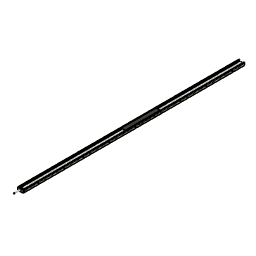
assembly-v21 (Autodesk Fusion 360 archive; units mm, degrees)
design "Linear actuator"
Autodesk Fusion 360 part; units mm, degrees
(part 1 of 2)
sketch "C section" plane through (0, 0, 0) normal (0, 1, 0) x (1, 0, 0)
  line L0 (0, 0) -> (40, 0)
  line L1 (40, 0) -> (40, -20)
  line L2 (0, -20) -> (0, 0)
  line L3 (5, -5) -> (35, -5)
  line L4 (0, -20) -> (5, -20) construction
  line L5 (0, -20) -> (5, -20)
  line L6 (35, -20) -> (40, -20)
  line L7 (34, -20) -> (34, -6.4559) construction
  line L8 (6, -6.4559) -> (6, -20) construction
  line L9 (5, -11) -> (35, -11) construction
  line L10 (5, -15) -> (35, -15) construction
  line L11 (6, -14.25) -> (5, -14.25)
  line L12 (5, -15.75) -> (6, -15.75)
  line L13 (6, -15.75) -> (6, -14.25)
  line L14 (5, -20) -> (5, -15.75)
  line L15 (5, -11.75) -> (6, -11.75)
  line L16 (6, -11.75) -> (6, -10.25)
  line L17 (5, -10.25) -> (6, -10.25)
  line L18 (20, 0) -> (20, -24.6236) construction
  line L19 (34, -14.25) -> (35, -14.25)
  line L20 (35, -15.75) -> (34, -15.75)
  line L21 (34, -15.75) -> (34, -14.25)
  line L22 (35, -11.75) -> (34, -11.75)
  line L23 (35, -10.25) -> (34, -10.25)
  line L24 (34, -11.75) -> (34, -10.25)
  line L25 (35, -15.75) -> (35, -20)
  line L26 (35, -5) -> (35, -10.25)
  line L27 (35, -11.75) -> (35, -14.25)
  line L28 (5, -14.25) -> (5, -11.75)
  line L29 (5, -10.25) -> (5, -5)
  point P0 (5, -15)
  dimension "d1" = 40
  dimension "d2" = 20
  dimension "d5" = 1
  dimension "d6" = 15
  dimension "d7" = 1.5
  dimension "d8" = 0.75
  dimension "d9" = 11
  dimension "d10" = 1.5
  dimension "d18" = 34
  constraint horizontal L0
  constraint vertical L1
  constraint vertical L2
  constraint coincident L0.start L2.end
  constraint vertical L7
  constraint vertical L8
  constraint coincident L9.start L14
  constraint perpendicular L9 L26
  constraint coincident P0 L14
  constraint perpendicular L10 L26
  constraint horizontal L11
  constraint parallel L11 L12
  constraint coincident P0 L10.start
  constraint coincident L8 L12.end
  constraint coincident L11.end L14
  constraint collinear L8 L13
  constraint collinear L14 L28
  constraint coincident L8 L15.end
  constraint perpendicular L8 L15
  constraint coincident L8 L16.end
  constraint perpendicular L9 L16
  constraint coincident L17.start L28
  constraint perpendicular L16 L17
  constraint symmetric L9 L15 L17
  constraint midpoint L0 L18.start
  constraint symmetric L11.start L18 L19.start
  constraint symmetric L12.end L18 L20.end
  constraint symmetric L12.start L18 L20.start
  constraint symmetric L11.end L18 L19.end
  constraint symmetric L15.start L18 L22.start
  constraint symmetric L15.end L18 L22.end
  constraint symmetric L16.end L18 L23.end
  constraint symmetric L17.start L18 L23.start
  constraint collinear L25 L26
  constraint collinear L26 L27
  constraint collinear L28 L29
  measures "d1" distance of L0.start L0.end
  measures "d2" distance of L0.start L2.start
  measures "d5" distance of L8 L14
  measures "d6" vertical distance of L0.start L10.start
  measures "d7" distance of L11.start L12.end
  measures "d8" distance of L10 L12.end
  measures "d9" distance of L0.start L9
  measures "d10" distance of L15.end L16.end
  measures "d18" horizontal distance of L0.start L7.end
extrude "Extrude1" add sketch "C section" along normal blind 1580 makes body 1
fillet "Fillet1" radius 2 2 edges at (5, 790, 5) (35, 790, 5) on bodies 1
fillet "Fillet2" radius 0.25 8 edges at (34, 790, 15.75) (34, 790, 14.25) (34, 790, 11.75) (34, 790, 10.25) (6, 790, 11.75) (6, 790, 10.25) (6, 790, 14.25) (6, 790, 15.75) on bodies 1
chamfer "Chamfer1" distance 1.5 angle 45 2 edges at (5, 790, 20) (35, 790, 20) on bodies 1
chamfer "Chamfer2" distance 0.5 angle 45 4 edges at (40, 790, 20) (40, 790, 0) (0, 790, 20) (0, 790, 0) on bodies 1
sketch "Rail" plane through (0, 0, 0) normal (0, 1, 0) x (1, 0, 0)
  line L0 (5.5, -20) -> (34.5, -20)
  line L1 (34.5, -6) -> (5.5, -6)
  line L2 (5, -18.5) -> (35, -18.5) construction
  line L3 (20, -18.5) -> (20, -21.5) construction
  line L4 (36.5, -20) -> (39.5, -20) construction
  line L5 (5, -15.75) -> (5.75, -15.75) construction
  line L6 (5.75, -14.25) -> (5, -14.25) construction
  line L7 (6, -15.5) -> (6, -14.5) construction
  arc A0 (5.75, -15.75) -> (6, -15.5) centre (5.75, -15.5) ccw construction
  arc A1 (6, -14.5) -> (5.75, -14.25) centre (5.75, -14.5) ccw construction
  line L8 (5, -11.75) -> (5.75, -11.75) construction
  arc A2 (5.75, -11.75) -> (6, -11.5) centre (5.75, -11.5) ccw construction
  arc A3 (6, -10.5) -> (5.75, -10.25) centre (5.75, -10.5) ccw construction
  line L9 (6, -11.5) -> (6, -10.5) construction
  line L10 (5, -10.25) -> (5.75, -10.25) construction
  line L11 (35, -15.75) -> (34.25, -15.75) construction
  arc A4 (34, -15.5) -> (34.25, -15.75) centre (34.25, -15.5) ccw construction
  line L12 (34, -15.5) -> (34, -14.5) construction
  arc A5 (34.25, -14.25) -> (34, -14.5) centre (34.25, -14.5) ccw construction
  line L13 (34.25, -14.25) -> (35, -14.25) construction
  line L14 (35, -11.75) -> (34.25, -11.75) construction
  arc A6 (34, -11.5) -> (34.25, -11.75) centre (34.25, -11.5) ccw construction
  line L15 (34, -11.5) -> (34, -10.5) construction
  arc A7 (34.25, -10.25) -> (34, -10.5) centre (34.25, -10.5) ccw construction
  line L16 (35, -10.25) -> (34.25, -10.25) construction
  line L17 (5, -16) -> (5.75, -16)
  arc A8 (5.75, -16) -> (6.25, -15.5) centre (5.75, -15.5) ccw
  line L18 (6.25, -15.5) -> (6.25, -14.5)
  arc A9 (6.25, -14.5) -> (5.75, -14) centre (5.75, -14.5) ccw
  line L19 (5.75, -14) -> (5, -14)
  line L20 (5, -12) -> (5.75, -12)
  arc A10 (5.75, -12) -> (6.25, -11.5) centre (5.75, -11.5) ccw
  line L21 (6.25, -11.5) -> (6.25, -10.5)
  arc A11 (6.25, -10.5) -> (5.75, -10) centre (5.75, -10.5) ccw
  line L22 (5, -10) -> (5.75, -10)
  line L23 (5.5, -16) -> (5.5, -20)
  line L24 (5.5, -6) -> (5.5, -10)
  line L25 (5.5, -12) -> (5.5, -14)
  line L26 (33.75, -15.5) -> (33.75, -14.5)
  arc A12 (33.75, -15.5) -> (34.25, -16) centre (34.25, -15.5) ccw
  line L27 (34.5, -16) -> (34.25, -16)
  line L28 (34.25, -14) -> (34.5, -14)
  arc A13 (34.25, -14) -> (33.75, -14.5) centre (34.25, -14.5) ccw
  arc A14 (33.75, -11.5) -> (34.25, -12) centre (34.25, -11.5) ccw
  line L29 (34.5, -12) -> (34.25, -12)
  line L30 (33.75, -11.5) -> (33.75, -10.5)
  arc A15 (34.25, -10) -> (33.75, -10.5) centre (34.25, -10.5) ccw
  line L31 (34.5, -10) -> (34.25, -10)
  line L32 (34.5, -20) -> (34.5, -16)
  line L33 (34.5, -14) -> (34.5, -12)
  line L34 (34.5, -10) -> (34.5, -6)
  point P0 (35, -18.5)
  point P1 (5, -18.5)
  dimension "d20" = 29
  dimension "d21" = 14
  dimension "d23" = 0.25
  dimension "d24" = 0.25
  constraint horizontal L0
  constraint vertical L32
  constraint horizontal L1
  constraint vertical L24
  constraint coincident P1 L2.start
  constraint coincident P0 L2.end
  constraint midpoint L2 L3.start
  constraint perpendicular L1 L3
  constraint midpoint L0 L3
  constraint collinear L0 L4
  constraint coincident L17 L23.start
  constraint collinear L23 L24
  constraint coincident L19 L25.end
  constraint collinear L24 L25
  constraint coincident L20 L25.start
  constraint coincident L22 L24.end
  constraint symmetric L3 L17.end A12.end
  constraint symmetric L3 A8.end L26.start
  constraint symmetric L3 A8 A12
  constraint symmetric L3 L18.end L26.end
  constraint symmetric L3 A9.end L28.start
  constraint symmetric L3 A9 A13
  constraint symmetric L3 L20.end A14.end
  constraint symmetric L3 A10.end A14.start
  constraint symmetric L3 A10 A14
  constraint symmetric L3 L21.end L30.end
  constraint symmetric L3 A11.end A15.start
  constraint symmetric L3 A11 A15
  constraint collinear L32 L33
  constraint collinear L33 L34
  measures "d20" distance of L0.start L0.end
  measures "d21" distance of L0.start L1.end
  measures "d23" distance of A0
extrude "Extrude2" add sketch "Rail" along normal blind 250 separate body makes body 2
sketch "Rail hole" plane through (0, 0, 0) normal (0, -1, 0) x (1, 0, 0)
  line L0 (34.5, 10) -> (34.25, 10)
  arc A0 (33.75, 10.5) -> (34.25, 10) centre (34.25, 10.5) ccw
  line L1 (33.75, 10.5) -> (33.75, 11.5)
  arc A1 (34.25, 12) -> (33.75, 11.5) centre (34.25, 11.5) ccw
  line L2 (34.25, 12) -> (34.5, 12)
  line L3 (34.5, 12) -> (34.5, 14)
  line L4 (34.5, 14) -> (34.25, 14)
  arc A2 (33.75, 14.5) -> (34.25, 14) centre (34.25, 14.5) ccw
  line L5 (33.75, 14.5) -> (33.75, 15.5)
  arc A3 (34.25, 16) -> (33.75, 15.5) centre (34.25, 15.5) ccw
  line L6 (34.25, 16) -> (34.5, 16)
  line L7 (34.5, 16) -> (34.5, 20)
  line L8 (34.5, 20) -> (5.5, 20)
  line L9 (5.5, 20) -> (5.5, 16)
  line L10 (5.5, 16) -> (5.75, 16)
  arc A4 (6.25, 15.5) -> (5.75, 16) centre (5.75, 15.5) ccw
  line L11 (6.25, 15.5) -> (6.25, 14.5)
  arc A5 (5.75, 14) -> (6.25, 14.5) centre (5.75, 14.5) ccw
  line L12 (5.75, 14) -> (5.5, 14)
  line L13 (5.5, 14) -> (5.5, 12)
  line L14 (5.5, 12) -> (5.75, 12)
  arc A6 (6.25, 11.5) -> (5.75, 12) centre (5.75, 11.5) ccw
  line L15 (6.25, 11.5) -> (6.25, 10.5)
  arc A7 (5.75, 10) -> (6.25, 10.5) centre (5.75, 10.5) ccw
  line L16 (5.75, 10) -> (5.5, 10)
  line L17 (5.5, 10) -> (5.5, 6)
  line L18 (5.5, 6) -> (34.5, 6)
  line L19 (34.5, 6) -> (34.5, 10)
  line L20 (5.5, 20) -> (34.5, 6) construction
  line L21 (34.5, 20) -> (5.5, 6) construction
  circle A8 centre (20, 13) radius 5.05
  dimension "d27" = 10.1
  constraint coincident L8.end L9.start
  constraint coincident L18.end L19.start
  constraint coincident L7.end L8.start
  constraint coincident L17.end L18.start
  constraint midpoint L20 A8.centre
  measures "d27" diameter of A8
fillet "Fillet3" radius 2 2 edges at (5.5, 125, 6) (34.5, 125, 6) on bodies 2
extrude "Extrude3" cut sketch "Rail hole" against normal up to surface (250 mm away) contours A8 bodies 2
chamfer "Chamfer3" distance 0.25 angle 45 2 edges at (15.2917, 0, 14.8262) (15.2917, 250, 11.1738) on bodies 2
sketch "Lead screw" plane through (0, 0, 0) normal (0, -1, 0) x (1, 0, 0)
  circle A0 centre (0, 0) radius 5
  dimension "d33" = 10
  constraint coincident A0.centre origin
  measures "d33" diameter of A0
extrude "Extrude4" add sketch "Lead screw" against normal blind 1630 separate body makes body 3
thread "Thread1" "ISO Metric Trapezoidal Threads 10.0 TR10x1.5 7e" major diameter 9.925 minor diameter 8.0605 pitch 1.5 angle 30 resizes the face on face at (4.8907, 1086.6667, -1.0396) on bodies 3
copy_body "Body->Comp1" bodies 1 removing the originals makes body 4 in component "C section"
copy_body "Body->Comp2" bodies 2 removing the originals makes body 5 in component "Rail"
copy_body "Body->Comp3" bodies 3 removing the originals makes body 6 in component "Lead screw"
sketch "Sketch5" plane through (0, 0, 0) normal (0, 1, 0) x (1, 0, 0)
  line L0 (0, -0.5) -> (0.5, 0)
  line L1 (0.5, 0) -> (39.5, 0)
  line L2 (39.5, 0) -> (40, -0.5)
  line L3 (40, -0.5) -> (40, -19.5)
  line L4 (40, -19.5) -> (39.5, -20)
  line L5 (39.5, -20) -> (36.5, -20)
  line L6 (36.5, -20) -> (35, -18.5)
  line L7 (35, -18.5) -> (35, -15.75)
  line L8 (35, -15.75) -> (34.25, -15.75)
  arc A0 (34, -15.5) -> (34.25, -15.75) centre (34.25, -15.5) ccw
  line L9 (34, -15.5) -> (34, -14.5)
  arc A1 (34.25, -14.25) -> (34, -14.5) centre (34.25, -14.5) ccw
  line L10 (34.25, -14.25) -> (35, -14.25)
  line L11 (35, -14.25) -> (35, -11.75)
  line L12 (35, -11.75) -> (34.25, -11.75)
  arc A2 (34, -11.5) -> (34.25, -11.75) centre (34.25, -11.5) ccw
  line L13 (34, -11.5) -> (34, -10.5)
  arc A3 (34.25, -10.25) -> (34, -10.5) centre (34.25, -10.5) ccw
  line L14 (34.25, -10.25) -> (35, -10.25)
  line L15 (35, -10.25) -> (35, -7)
  arc A4 (35, -7) -> (33, -5) centre (33, -7) ccw
  line L16 (33, -5) -> (7, -5)
  arc A5 (7, -5) -> (5, -7) centre (7, -7) ccw
  line L17 (5, -7) -> (5, -10.25)
  line L18 (5, -10.25) -> (5.75, -10.25)
  arc A6 (6, -10.5) -> (5.75, -10.25) centre (5.75, -10.5) ccw
  line L19 (6, -10.5) -> (6, -11.5)
  arc A7 (5.75, -11.75) -> (6, -11.5) centre (5.75, -11.5) ccw
  line L20 (5.75, -11.75) -> (5, -11.75)
  line L21 (5, -11.75) -> (5, -14.25)
  line L22 (5, -14.25) -> (5.75, -14.25)
  arc A8 (6, -14.5) -> (5.75, -14.25) centre (5.75, -14.5) ccw
  line L23 (6, -14.5) -> (6, -15.5)
  arc A9 (5.75, -15.75) -> (6, -15.5) centre (5.75, -15.5) ccw
  line L24 (5.75, -15.75) -> (5, -15.75)
  line L25 (5, -15.75) -> (5, -18.5)
  line L26 (5, -18.5) -> (3.5, -20)
  line L27 (3.5, -20) -> (0.5, -20)
  line L28 (0.5, -20) -> (0, -19.5)
  line L29 (0, -19.5) -> (0, -0.5)
  circle A10 centre (20, -13) radius 5.05
  line L30 (3.5, -20) -> (36.5, -20)
  constraint coincident L26.end L27.start
  constraint coincident L5.end L6.start
extrude "Extrude1'" add sketch "Sketch5" against normal blind 10 separate body contours L0 L1 L2 L3 L4 L5 L6 L7 L8 A0 L9 A1 L10 L11 L12 A2 L13 A3 L14 L15 A4 L16 A5 L17 L18 A6 L19 A7 L20 L21 L22 A8 L23 A9 L24 L25 L26 L27 L28 L29 | L6 L7 L8 A0 L9 A1 L10 L11 L12 A2 L13 A3 L14 L15 A4 L16 A5 L17 L18 A6 L19 A7 L20 L21 L22 A8 L23 A9 L24 L25 L26 L30 | A10 makes body 7 in component "C section"
sketch "Sketch6" plane through (0, 1580, 0) normal (0, 1, 0) x (-1, 0, 0)
  line L0 (-0.5, 0) -> (0, 0.5)
  line L1 (0, 0.5) -> (0, 19.5)
  line L2 (0, 19.5) -> (-0.5, 20)
  line L3 (-0.5, 20) -> (-3.5, 20)
  line L4 (-3.5, 20) -> (-5, 18.5)
  line L5 (-5, 18.5) -> (-5, 15.75)
  line L6 (-5, 15.75) -> (-5.75, 15.75)
  arc A0 (-5.75, 15.75) -> (-6, 15.5) centre (-5.75, 15.5) ccw
  line L7 (-6, 15.5) -> (-6, 14.5)
  arc A1 (-6, 14.5) -> (-5.75, 14.25) centre (-5.75, 14.5) ccw
  line L8 (-5.75, 14.25) -> (-5, 14.25)
  line L9 (-5, 14.25) -> (-5, 11.75)
  line L10 (-5, 11.75) -> (-5.75, 11.75)
  arc A2 (-5.75, 11.75) -> (-6, 11.5) centre (-5.75, 11.5) ccw
  line L11 (-6, 11.5) -> (-6, 10.5)
  arc A3 (-6, 10.5) -> (-5.75, 10.25) centre (-5.75, 10.5) ccw
  line L12 (-5.75, 10.25) -> (-5, 10.25)
  line L13 (-5, 10.25) -> (-5, 7)
  arc A4 (-7, 5) -> (-5, 7) centre (-7, 7) ccw
  line L14 (-7, 5) -> (-33, 5)
  arc A5 (-35, 7) -> (-33, 5) centre (-33, 7) ccw
  line L15 (-35, 7) -> (-35, 10.25)
  line L16 (-35, 10.25) -> (-34.25, 10.25)
  arc A6 (-34.25, 10.25) -> (-34, 10.5) centre (-34.25, 10.5) ccw
  line L17 (-34, 10.5) -> (-34, 11.5)
  arc A7 (-34, 11.5) -> (-34.25, 11.75) centre (-34.25, 11.5) ccw
  line L18 (-34.25, 11.75) -> (-35, 11.75)
  line L19 (-35, 11.75) -> (-35, 14.25)
  line L20 (-35, 14.25) -> (-34.25, 14.25)
  arc A8 (-34.25, 14.25) -> (-34, 14.5) centre (-34.25, 14.5) ccw
  line L21 (-34, 14.5) -> (-34, 15.5)
  arc A9 (-34, 15.5) -> (-34.25, 15.75) centre (-34.25, 15.5) ccw
  line L22 (-34.25, 15.75) -> (-35, 15.75)
  line L23 (-35, 15.75) -> (-35, 18.5)
  line L24 (-35, 18.5) -> (-36.5, 20)
  line L25 (-36.5, 20) -> (-39.5, 20)
  line L26 (-39.5, 20) -> (-40, 19.5)
  line L27 (-40, 19.5) -> (-40, 0.5)
  line L28 (-40, 0.5) -> (-39.5, 0)
  line L29 (-39.5, 0) -> (-0.5, 0)
  line L30 (-3.5, 20) -> (-36.5, 20)
  circle A10 centre (-20, 13) radius 5
  constraint coincident L3.end L4.start
  constraint coincident L24.end L25.start
extrude "Extrude5" add sketch "Sketch6" along normal blind 10 separate body contours L0 L1 L2 L3 L4 L5 L6 A0 L7 A1 L8 L9 L10 A2 L11 A3 L12 L13 A4 L14 A5 L15 L16 A6 L17 A7 L18 L19 L20 A8 L21 A9 L22 L23 L24 L25 L26 L27 L28 L29 | L4 L5 L6 A0 L7 A1 L8 L9 L10 A2 L11 A3 L12 L13 A4 L14 A5 L15 L16 A6 L17 A7 L18 L19 L20 A8 L21 A9 L22 L23 L24 L30 | A10 makes body 8
extrude "Extrude2'" [no effect] in component "C section"
copy_body "Body->Comp4" bodies 8 removing the originals makes body 9 in component "End closure 2"
sketch "Sketch7" plane through (0, 0, 0) normal (0, 1, 0) x (-1, 0, 0)
  line L0 (-0.5, 20) -> (-39.5, 20)
  line L1 (-39.5, 20) -> (-40, 19.5)
  line L2 (-40, 19.5) -> (-40, 0.5)
  line L3 (-40, 0.5) -> (-39.5, 0)
  line L4 (-39.5, 0) -> (-0.5, 0)
  line L5 (-0.5, 0) -> (0, 0.5)
  line L6 (0, 0.5) -> (0, 19.5)
  line L7 (0, 19.5) -> (-0.5, 20)
  circle A0 centre (-20, 13) radius 7
  circle A1 centre (-20, 13) radius 5.25
  dimension "d44" = 14
  dimension "d45" = 10.5
  constraint concentric A0 A1
  measures "d44" diameter of A0
  measures "d45" diameter of A1
sketch "Sketch8" plane through (0, 1580, 0) normal (0, -1, 0) x (1, 0, 0)
  line L0 (39.5, 20) -> (0.5, 20)
  line L1 (0.5, 20) -> (0, 19.5)
  line L2 (0, 19.5) -> (0, 0.5)
  line L3 (0, 0.5) -> (0.5, 0)
  line L4 (0.5, 0) -> (39.5, 0)
  line L5 (39.5, 0) -> (40, 0.5)
  line L6 (40, 0.5) -> (40, 19.5)
  line L7 (40, 19.5) -> (39.5, 20)
  circle A0 centre (20, 13) radius 7
  circle A1 centre (20, 13) radius 5
  dimension "d50" = 14
  dimension "d51" = 10
  constraint concentric A0 A1
  measures "d50" diameter of A0
  measures "d51" diameter of A1
extrude "Extrude1''" add sketch "Sketch8" along normal blind 5 separate body contours A0 makes body 10 in component "End closure 2"
sketch "Sketch9" plane through (0, 0, 0) normal (0, 1, 0) x (-1, 0, 0)
  line L0 (-0.5, 20) -> (-39.5, 20)
  line L1 (-39.5, 20) -> (-40, 19.5)
  line L2 (-40, 19.5) -> (-40, 0.5)
  line L3 (-40, 0.5) -> (-39.5, 0)
  line L4 (-39.5, 0) -> (-0.5, 0)
  line L5 (-0.5, 0) -> (0, 0.5)
  line L6 (0, 0.5) -> (0, 19.5)
  line L7 (0, 19.5) -> (-0.5, 20)
  circle A0 centre (-20, 13) radius 7
  circle A1 centre (-20, 13) radius 5.25
  dimension "d62" = 14
  dimension "d63" = 10.5
  constraint concentric A0 A1
  measures "d62" diameter of A0
  measures "d63" diameter of A1
extrude "Extrude6" add sketch "Sketch9" along normal blind 5 separate body contours A0 makes body 11
copy_body "Body->Comp5" bodies 11 removing the originals makes body 12 in component "Bearing 1"
copy_body "Body->Comp1'" bodies 10 removing the originals makes body 13 in component "Bearing 2"
sketch "Sketch10" plane through (0, 0, 0) normal (0, 1, 0) x (-1, 0, 0)
  line L0 (-0.5, 20) -> (-39.5, 20)
  line L1 (-39.5, 20) -> (-40, 19.5)
  line L2 (-40, 19.5) -> (-40, 0.5)
  line L3 (-40, 0.5) -> (-39.5, 0)
  line L4 (-39.5, 0) -> (-0.5, 0)
  line L5 (-0.5, 0) -> (0, 0.5)
  line L6 (0, 0.5) -> (0, 19.5)
  line L7 (0, 19.5) -> (-0.5, 20)
  circle A0 centre (-20, 13) radius 5.25
extrude "Extrude3'" cut sketch "Sketch10" against normal blind 10 contours A0 bodies 7 in component "C section"
component "C section" placed x (1, 0, 0) y (0, 1, 0) z (0, 0, 1) at (0, 0, 0)
component "Rail" placed x (1, 0, 0) y (0, 1, 0) z (0, 0, 1) at (0, 728.6375, 0)
component "Lead screw" placed x (1, 0, 0) y (0, 1, 0) z (0, 0, 1) at (20, -55, 13)
component "End closure 2" placed x (1, 0, 0) y (0, 1, 0) z (0, 0, 1) at (0, 0, 0)
component "Bearing 1" placed x (1, 0, 0) y (0, 1, 0) z (0, 0, 1) at (0, 0, 0)
component "Bearing 2" placed x (1, 0, 0) y (0, 1, 0) z (0, 0, 1) at (0, 0, 0) in component "End closure 2"
equation "d11 = 1600 mm - 20 mm"
named bodies: "C section", "Rail", "Lead screw", "End closure", "End closure 2"

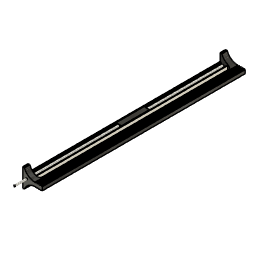
design "Linear actuator new"
Autodesk Fusion 360 part; units mm, degrees
sketch "C section" plane through (0, 0, 0) normal (0, 1, 0) x (1, 0, 0)
  line L0 (0, 0) -> (40, 0)
  line L1 (40, 0) -> (40, -20)
  line L2 (0, -20) -> (0, 0)
  line L3 (5, -5) -> (35, -5)
  line L4 (0, -20) -> (5, -20) construction
  line L5 (0, -20) -> (5, -20)
  line L6 (35, -20) -> (40, -20)
  line L7 (34, -20) -> (34, -6.4559) construction
  line L8 (6, -6.4559) -> (6, -20) construction
  line L9 (5, -11) -> (35, -11) construction
  line L10 (5, -15) -> (35, -15) construction
  line L11 (6, -14.25) -> (5, -14.25)
  line L12 (5, -15.75) -> (6, -15.75)
  line L13 (6, -15.75) -> (6, -14.25)
  line L14 (5, -20) -> (5, -15.75)
  line L15 (5, -11.75) -> (6, -11.75)
  line L16 (6, -11.75) -> (6, -10.25)
  line L17 (5, -10.25) -> (6, -10.25)
  line L18 (20, 0) -> (20, -24.6236) construction
  line L19 (34, -14.25) -> (35, -14.25)
  line L20 (35, -15.75) -> (34, -15.75)
  line L21 (34, -15.75) -> (34, -14.25)
  line L22 (35, -11.75) -> (34, -11.75)
  line L23 (35, -10.25) -> (34, -10.25)
  line L24 (34, -11.75) -> (34, -10.25)
  line L25 (35, -15.75) -> (35, -20)
  line L26 (35, -5) -> (35, -10.25)
  line L27 (35, -11.75) -> (35, -14.25)
  line L28 (5, -14.25) -> (5, -11.75)
  line L29 (5, -10.25) -> (5, -5)
  point P0 (5, -15)
  dimension "d1" = 40
  dimension "d2" = 20
  dimension "d5" = 1
  dimension "d6" = 15
  dimension "d7" = 1.5
  dimension "d8" = 0.75
  dimension "d9" = 11
  dimension "d10" = 1.5
  dimension "d18" = 34
  constraint horizontal L0
  constraint vertical L1
  constraint vertical L2
  constraint coincident L0.start L2.end
  constraint vertical L7
  constraint vertical L8
  constraint coincident L9.start L14
  constraint perpendicular L9 L26
  constraint coincident P0 L14
  constraint perpendicular L10 L26
  constraint horizontal L11
  constraint parallel L11 L12
  constraint coincident P0 L10.start
  constraint coincident L8 L12.end
  constraint coincident L11.end L14
  constraint collinear L8 L13
  constraint collinear L14 L28
  constraint coincident L8 L15.end
  constraint perpendicular L8 L15
  constraint coincident L8 L16.end
  constraint perpendicular L9 L16
  constraint coincident L17.start L28
  constraint perpendicular L16 L17
  constraint symmetric L9 L15 L17
  constraint midpoint L0 L18.start
  constraint symmetric L11.start L18 L19.start
  constraint symmetric L12.end L18 L20.end
  constraint symmetric L12.start L18 L20.start
  constraint symmetric L11.end L18 L19.end
  constraint symmetric L15.start L18 L22.start
  constraint symmetric L15.end L18 L22.end
  constraint symmetric L16.end L18 L23.end
  constraint symmetric L17.start L18 L23.start
  constraint collinear L25 L26
  constraint collinear L26 L27
  constraint collinear L28 L29
  measures "d1" distance of L0.start L0.end
  measures "d2" distance of L0.start L2.start
  measures "d5" distance of L8 L14
  measures "d6" vertical distance of L0.start L10.start
  measures "d7" distance of L11.start L12.end
  measures "d8" distance of L10 L12.end
  measures "d9" distance of L0.start L9
  measures "d10" distance of L15.end L16.end
  measures "d18" horizontal distance of L0.start L7.end
extrude "Extrude1" add sketch "C section" along normal blind 1031 makes body 1
fillet "Fillet1" radius 2 2 edges at (5, 515.5, 5) (35, 515.5, 5) on bodies 1
fillet "Fillet2" radius 0.25 8 edges at (34, 515.5, 15.75) (34, 515.5, 14.25) (34, 515.5, 11.75) (34, 515.5, 10.25) (6, 515.5, 11.75) (6, 515.5, 10.25) (6, 515.5, 14.25) (6, 515.5, 15.75) on bodies 1
chamfer "Chamfer1" distance 1.5 angle 45 2 edges at (5, 515.5, 20) (35, 515.5, 20) on bodies 1
chamfer "Chamfer2" distance 0.5 angle 45 4 edges at (40, 515.5, 20) (40, 515.5, 0) (0, 515.5, 20) (0, 515.5, 0) on bodies 1
sketch "Rail" plane through (0, 0, 0) normal (0, 1, 0) x (1, 0, 0)
  line L0 (5.5, -20) -> (34.5, -20)
  line L1 (34.5, -6) -> (5.5, -6)
  line L2 (5, -18.5) -> (35, -18.5) construction
  line L3 (20, -18.5) -> (20, -21.5) construction
  line L4 (36.5, -20) -> (39.5, -20) construction
  line L5 (5, -15.75) -> (5.75, -15.75) construction
  line L6 (5.75, -14.25) -> (5, -14.25) construction
  line L7 (6, -15.5) -> (6, -14.5) construction
  arc A0 (5.75, -15.75) -> (6, -15.5) centre (5.75, -15.5) ccw construction
  arc A1 (6, -14.5) -> (5.75, -14.25) centre (5.75, -14.5) ccw construction
  line L8 (5, -11.75) -> (5.75, -11.75) construction
  arc A2 (5.75, -11.75) -> (6, -11.5) centre (5.75, -11.5) ccw construction
  arc A3 (6, -10.5) -> (5.75, -10.25) centre (5.75, -10.5) ccw construction
  line L9 (6, -11.5) -> (6, -10.5) construction
  line L10 (5, -10.25) -> (5.75, -10.25) construction
  line L11 (35, -15.75) -> (34.25, -15.75) construction
  arc A4 (34, -15.5) -> (34.25, -15.75) centre (34.25, -15.5) ccw construction
  line L12 (34, -15.5) -> (34, -14.5) construction
  arc A5 (34.25, -14.25) -> (34, -14.5) centre (34.25, -14.5) ccw construction
  line L13 (34.25, -14.25) -> (35, -14.25) construction
  line L14 (35, -11.75) -> (34.25, -11.75) construction
  arc A6 (34, -11.5) -> (34.25, -11.75) centre (34.25, -11.5) ccw construction
  line L15 (34, -11.5) -> (34, -10.5) construction
  arc A7 (34.25, -10.25) -> (34, -10.5) centre (34.25, -10.5) ccw construction
  line L16 (35, -10.25) -> (34.25, -10.25) construction
  line L17 (5, -16) -> (5.75, -16)
  arc A8 (5.75, -16) -> (6.25, -15.5) centre (5.75, -15.5) ccw
  line L18 (6.25, -15.5) -> (6.25, -14.5)
  arc A9 (6.25, -14.5) -> (5.75, -14) centre (5.75, -14.5) ccw
  line L19 (5.75, -14) -> (5, -14)
  line L20 (5, -12) -> (5.75, -12)
  arc A10 (5.75, -12) -> (6.25, -11.5) centre (5.75, -11.5) ccw
  line L21 (6.25, -11.5) -> (6.25, -10.5)
  arc A11 (6.25, -10.5) -> (5.75, -10) centre (5.75, -10.5) ccw
  line L22 (5, -10) -> (5.75, -10)
  line L23 (5.5, -16) -> (5.5, -20)
  line L24 (5.5, -6) -> (5.5, -10)
  line L25 (5.5, -12) -> (5.5, -14)
  line L26 (33.75, -15.5) -> (33.75, -14.5)
  arc A12 (33.75, -15.5) -> (34.25, -16) centre (34.25, -15.5) ccw
  line L27 (34.5, -16) -> (34.25, -16)
  line L28 (34.25, -14) -> (34.5, -14)
  arc A13 (34.25, -14) -> (33.75, -14.5) centre (34.25, -14.5) ccw
  arc A14 (33.75, -11.5) -> (34.25, -12) centre (34.25, -11.5) ccw
  line L29 (34.5, -12) -> (34.25, -12)
  line L30 (33.75, -11.5) -> (33.75, -10.5)
  arc A15 (34.25, -10) -> (33.75, -10.5) centre (34.25, -10.5) ccw
  line L31 (34.5, -10) -> (34.25, -10)
  line L32 (34.5, -20) -> (34.5, -16)
  line L33 (34.5, -14) -> (34.5, -12)
  line L34 (34.5, -10) -> (34.5, -6)
  point P0 (35, -18.5)
  point P1 (5, -18.5)
  dimension "d20" = 29
  dimension "d21" = 14
  dimension "d23" = 0.25
  dimension "d24" = 0.25
  constraint horizontal L0
  constraint vertical L32
  constraint horizontal L1
  constraint vertical L24
  constraint coincident P1 L2.start
  constraint coincident P0 L2.end
  constraint midpoint L2 L3.start
  constraint perpendicular L1 L3
  constraint midpoint L0 L3
  constraint collinear L0 L4
  constraint coincident L17 L23.start
  constraint collinear L23 L24
  constraint coincident L19 L25.end
  constraint collinear L24 L25
  constraint coincident L20 L25.start
  constraint coincident L22 L24.end
  constraint symmetric L3 L17.end A12.end
  constraint symmetric L3 A8.end L26.start
  constraint symmetric L3 A8 A12
  constraint symmetric L3 L18.end L26.end
  constraint symmetric L3 A9.end L28.start
  constraint symmetric L3 A9 A13
  constraint symmetric L3 L20.end A14.end
  constraint symmetric L3 A10.end A14.start
  constraint symmetric L3 A10 A14
  constraint symmetric L3 L21.end L30.end
  constraint symmetric L3 A11.end A15.start
  constraint symmetric L3 A11 A15
  constraint collinear L32 L33
  constraint collinear L33 L34
  measures "d20" distance of L0.start L0.end
  measures "d21" distance of L0.start L1.end
  measures "d23" distance of A0
extrude "Extrude2" add sketch "Rail" along normal blind 150 separate body makes body 2
sketch "Rail hole" plane through (0, 0, 0) normal (0, -1, 0) x (1, 0, 0)
  line L0 (34.5, 10) -> (34.25, 10)
  arc A0 (33.75, 10.5) -> (34.25, 10) centre (34.25, 10.5) ccw
  line L1 (33.75, 10.5) -> (33.75, 11.5)
  arc A1 (34.25, 12) -> (33.75, 11.5) centre (34.25, 11.5) ccw
  line L2 (34.25, 12) -> (34.5, 12)
  line L3 (34.5, 12) -> (34.5, 14)
  line L4 (34.5, 14) -> (34.25, 14)
  arc A2 (33.75, 14.5) -> (34.25, 14) centre (34.25, 14.5) ccw
  line L5 (33.75, 14.5) -> (33.75, 15.5)
  arc A3 (34.25, 16) -> (33.75, 15.5) centre (34.25, 15.5) ccw
  line L6 (34.25, 16) -> (34.5, 16)
  line L7 (34.5, 16) -> (34.5, 20)
  line L8 (34.5, 20) -> (5.5, 20)
  line L9 (5.5, 20) -> (5.5, 16)
  line L10 (5.5, 16) -> (5.75, 16)
  arc A4 (6.25, 15.5) -> (5.75, 16) centre (5.75, 15.5) ccw
  line L11 (6.25, 15.5) -> (6.25, 14.5)
  arc A5 (5.75, 14) -> (6.25, 14.5) centre (5.75, 14.5) ccw
  line L12 (5.75, 14) -> (5.5, 14)
  line L13 (5.5, 14) -> (5.5, 12)
  line L14 (5.5, 12) -> (5.75, 12)
  arc A6 (6.25, 11.5) -> (5.75, 12) centre (5.75, 11.5) ccw
  line L15 (6.25, 11.5) -> (6.25, 10.5)
  arc A7 (5.75, 10) -> (6.25, 10.5) centre (5.75, 10.5) ccw
  line L16 (5.75, 10) -> (5.5, 10)
  line L17 (5.5, 10) -> (5.5, 6)
  line L18 (5.5, 6) -> (34.5, 6)
  line L19 (34.5, 6) -> (34.5, 10)
  line L20 (5.5, 20) -> (34.5, 6) construction
  line L21 (34.5, 20) -> (5.5, 6) construction
  circle A8 centre (20, 13) radius 5.05
  dimension "d27" = 10.1
  constraint coincident L8.end L9.start
  constraint coincident L18.end L19.start
  constraint coincident L7.end L8.start
  constraint coincident L17.end L18.start
  constraint midpoint L20 A8.centre
  measures "d27" diameter of A8
fillet "Fillet3" radius 2 2 edges at (5.5, 75, 6) (34.5, 75, 6) on bodies 2
extrude "Extrude3" cut sketch "Rail hole" against normal blind 100 contours A8 bodies 2
chamfer "Chamfer3" distance 0.25 angle 45 2 edges at (15.2917, 0, 14.8262) (15.2917, 100, 14.8262) on bodies 2
sketch "Lead screw" plane through (0, 0, 0) normal (0, -1, 0) x (1, 0, 0)
  circle A0 centre (0, 0) radius 5
  dimension "d33" = 10
  constraint coincident A0.centre origin
  measures "d33" diameter of A0
extrude "Extrude4" add sketch "Lead screw" against normal blind 1119 separate body makes body 3
thread "Thread1" "ISO Metric Trapezoidal Threads 10.0 TR10x1.5 7e" major diameter 9.925 minor diameter 8.0605 pitch 1.5 angle 30 resizes the face on face at (4.9513, 746, -0.6959) on bodies 3
copy_body "Body->Comp1" bodies 1 removing the originals makes body 4 in component "C section"
copy_body "Body->Comp2" bodies 2 removing the originals makes body 5 in component "Rail"
copy_body "Body->Comp3" bodies 3 removing the originals makes body 6 in component "Lead screw"
sketch "Sketch5" plane through (0, 0, 0) normal (0, 1, 0) x (1, 0, 0)
  line L0 (0, -0.5) -> (0.5, 0)
  line L1 (0.5, 0) -> (39.5, 0)
  line L2 (39.5, 0) -> (40, -0.5)
  line L3 (40, -0.5) -> (40, -19.5)
  line L4 (40, -19.5) -> (39.5, -20)
  line L5 (39.5, -20) -> (36.5, -20)
  line L6 (36.5, -20) -> (35, -18.5)
  line L7 (35, -18.5) -> (35, -15.75)
  line L8 (35, -15.75) -> (34.25, -15.75)
  arc A0 (34, -15.5) -> (34.25, -15.75) centre (34.25, -15.5) ccw
  line L9 (34, -15.5) -> (34, -14.5)
  arc A1 (34.25, -14.25) -> (34, -14.5) centre (34.25, -14.5) ccw
  line L10 (34.25, -14.25) -> (35, -14.25)
  line L11 (35, -14.25) -> (35, -11.75)
  line L12 (35, -11.75) -> (34.25, -11.75)
  arc A2 (34, -11.5) -> (34.25, -11.75) centre (34.25, -11.5) ccw
  line L13 (34, -11.5) -> (34, -10.5)
  arc A3 (34.25, -10.25) -> (34, -10.5) centre (34.25, -10.5) ccw
  line L14 (34.25, -10.25) -> (35, -10.25)
  line L15 (35, -10.25) -> (35, -7)
  arc A4 (35, -7) -> (33, -5) centre (33, -7) ccw
  line L16 (33, -5) -> (7, -5)
  arc A5 (7, -5) -> (5, -7) centre (7, -7) ccw
  line L17 (5, -7) -> (5, -10.25)
  line L18 (5, -10.25) -> (5.75, -10.25)
  arc A6 (6, -10.5) -> (5.75, -10.25) centre (5.75, -10.5) ccw
  line L19 (6, -10.5) -> (6, -11.5)
  arc A7 (5.75, -11.75) -> (6, -11.5) centre (5.75, -11.5) ccw
  line L20 (5.75, -11.75) -> (5, -11.75)
  line L21 (5, -11.75) -> (5, -14.25)
  line L22 (5, -14.25) -> (5.75, -14.25)
  arc A8 (6, -14.5) -> (5.75, -14.25) centre (5.75, -14.5) ccw
  line L23 (6, -14.5) -> (6, -15.5)
  arc A9 (5.75, -15.75) -> (6, -15.5) centre (5.75, -15.5) ccw
  line L24 (5.75, -15.75) -> (5, -15.75)
  line L25 (5, -15.75) -> (5, -18.5)
  line L26 (5, -18.5) -> (3.5, -20)
  line L27 (3.5, -20) -> (0.5, -20)
  line L28 (0.5, -20) -> (0, -19.5)
  line L29 (0, -19.5) -> (0, -0.5)
  circle A10 centre (20, -13) radius 5.05
  line L30 (3.5, -20) -> (36.5, -20)
  constraint coincident L26.end L27.start
  constraint coincident L5.end L6.start
extrude "Extrude1'" add sketch "Sketch5" against normal blind 29 separate body contours L0 L1 L2 L3 L4 L5 L6 L7 L8 A0 L9 A1 L10 L11 L12 A2 L13 A3 L14 L15 A4 L16 A5 L17 L18 A6 L19 A7 L20 L21 L22 A8 L23 A9 L24 L25 L26 L27 L28 L29 | L6 L7 L8 A0 L9 A1 L10 L11 L12 A2 L13 A3 L14 L15 A4 L16 A5 L17 L18 A6 L19 A7 L20 L21 L22 A8 L23 A9 L24 L25 L26 L30 | A10 makes body 7 in component "C section"
sketch "Sketch6" plane through (0, 1031, 0) normal (0, 1, 0) x (-1, 0, 0)
  line L0 (-0.5, 0) -> (0, 0.5)
  line L1 (0, 0.5) -> (0, 19.5)
  line L2 (0, 19.5) -> (-0.5, 20)
  line L3 (-0.5, 20) -> (-3.5, 20)
  line L4 (-3.5, 20) -> (-5, 18.5)
  line L5 (-5, 18.5) -> (-5, 15.75)
  line L6 (-5, 15.75) -> (-5.75, 15.75)
  arc A0 (-5.75, 15.75) -> (-6, 15.5) centre (-5.75, 15.5) ccw
  line L7 (-6, 15.5) -> (-6, 14.5)
  arc A1 (-6, 14.5) -> (-5.75, 14.25) centre (-5.75, 14.5) ccw
  line L8 (-5.75, 14.25) -> (-5, 14.25)
  line L9 (-5, 14.25) -> (-5, 11.75)
  line L10 (-5, 11.75) -> (-5.75, 11.75)
  arc A2 (-5.75, 11.75) -> (-6, 11.5) centre (-5.75, 11.5) ccw
  line L11 (-6, 11.5) -> (-6, 10.5)
  arc A3 (-6, 10.5) -> (-5.75, 10.25) centre (-5.75, 10.5) ccw
  line L12 (-5.75, 10.25) -> (-5, 10.25)
  line L13 (-5, 10.25) -> (-5, 7)
  arc A4 (-7, 5) -> (-5, 7) centre (-7, 7) ccw
  line L14 (-7, 5) -> (-33, 5)
  arc A5 (-35, 7) -> (-33, 5) centre (-33, 7) ccw
  line L15 (-35, 7) -> (-35, 10.25)
  line L16 (-35, 10.25) -> (-34.25, 10.25)
  arc A6 (-34.25, 10.25) -> (-34, 10.5) centre (-34.25, 10.5) ccw
  line L17 (-34, 10.5) -> (-34, 11.5)
  arc A7 (-34, 11.5) -> (-34.25, 11.75) centre (-34.25, 11.5) ccw
  line L18 (-34.25, 11.75) -> (-35, 11.75)
  line L19 (-35, 11.75) -> (-35, 14.25)
  line L20 (-35, 14.25) -> (-34.25, 14.25)
  arc A8 (-34.25, 14.25) -> (-34, 14.5) centre (-34.25, 14.5) ccw
  line L21 (-34, 14.5) -> (-34, 15.5)
  arc A9 (-34, 15.5) -> (-34.25, 15.75) centre (-34.25, 15.5) ccw
  line L22 (-34.25, 15.75) -> (-35, 15.75)
  line L23 (-35, 15.75) -> (-35, 18.5)
  line L24 (-35, 18.5) -> (-36.5, 20)
  line L25 (-36.5, 20) -> (-39.5, 20)
  line L26 (-39.5, 20) -> (-40, 19.5)
  line L27 (-40, 19.5) -> (-40, 0.5)
  line L28 (-40, 0.5) -> (-39.5, 0)
  line L29 (-39.5, 0) -> (-0.5, 0)
  line L30 (-3.5, 20) -> (-36.5, 20)
  circle A10 centre (-20, 13) radius 5
  constraint coincident L3.end L4.start
  constraint coincident L24.end L25.start
extrude "Extrude5" add sketch "Sketch6" along normal blind 29 separate body contours L0 L1 L2 L3 L4 L5 L6 A0 L7 A1 L8 L9 L10 A2 L11 A3 L12 L13 A4 L14 A5 L15 L16 A6 L17 A7 L18 L19 L20 A8 L21 A9 L22 L23 L24 L25 L26 L27 L28 L29 | L4 L5 L6 A0 L7 A1 L8 L9 L10 A2 L11 A3 L12 L13 A4 L14 A5 L15 L16 A6 L17 A7 L18 L19 L20 A8 L21 A9 L22 L23 L24 L30 | A10 makes body 8
extrude "Extrude2'" [no effect] in component "C section"
copy_body "Body->Comp4" bodies 8 removing the originals makes body 9 in component "End closure 2"
sketch "Sketch7" plane through (0, 0, 0) normal (0, 1, 0) x (-1, 0, 0)
  line L0 (-0.5, 20) -> (-39.5, 20)
  line L1 (-39.5, 20) -> (-40, 19.5)
  line L2 (-40, 19.5) -> (-40, 0.5)
  line L3 (-40, 0.5) -> (-39.5, 0)
  line L4 (-39.5, 0) -> (-0.5, 0)
  line L5 (-0.5, 0) -> (0, 0.5)
  line L6 (0, 0.5) -> (0, 19.5)
  line L7 (0, 19.5) -> (-0.5, 20)
  circle A0 centre (-20, 13) radius 7
  circle A1 centre (-20, 13) radius 5.25
  dimension "d44" = 14
  dimension "d45" = 10.5
  constraint concentric A0 A1
  measures "d44" diameter of A0
  measures "d45" diameter of A1
sketch "Sketch8" plane through (0, 1031, 0) normal (0, -1, 0) x (1, 0, 0)
  line L0 (39.5, 20) -> (0.5, 20)
  line L1 (0.5, 20) -> (0, 19.5)
  line L2 (0, 19.5) -> (0, 0.5)
  line L3 (0, 0.5) -> (0.5, 0)
  line L4 (0.5, 0) -> (39.5, 0)
  line L5 (39.5, 0) -> (40, 0.5)
  line L6 (40, 0.5) -> (40, 19.5)
  line L7 (40, 19.5) -> (39.5, 20)
  circle A0 centre (20, 13) radius 7
  circle A1 centre (20, 13) radius 5
  dimension "d50" = 14
  dimension "d51" = 10
  constraint concentric A0 A1
  measures "d50" diameter of A0
  measures "d51" diameter of A1
extrude "Extrude1''" add sketch "Sketch8" along normal blind 5 separate body contours A0 makes body 10 in component "End closure 2"
sketch "Sketch9" plane through (0, 0, 0) normal (0, 1, 0) x (-1, 0, 0)
  line L0 (-0.5, 20) -> (-39.5, 20)
  line L1 (-39.5, 20) -> (-40, 19.5)
  line L2 (-40, 19.5) -> (-40, 0.5)
  line L3 (-40, 0.5) -> (-39.5, 0)
  line L4 (-39.5, 0) -> (-0.5, 0)
  line L5 (-0.5, 0) -> (0, 0.5)
  line L6 (0, 0.5) -> (0, 19.5)
  line L7 (0, 19.5) -> (-0.5, 20)
  circle A0 centre (-20, 13) radius 7
  circle A1 centre (-20, 13) radius 5.25
  dimension "d62" = 14
  dimension "d63" = 10.5
  constraint concentric A0 A1
  measures "d62" diameter of A0
  measures "d63" diameter of A1
extrude "Extrude6" add sketch "Sketch9" along normal blind 5 separate body contours A0 makes body 11
copy_body "Body->Comp5" bodies 11 removing the originals makes body 12 in component "Bearing 1"
copy_body "Body->Comp1'" bodies 10 removing the originals makes body 13 in component "Bearing 2"
sketch "Sketch10" plane through (0, 0, 0) normal (0, 1, 0) x (-1, 0, 0)
  line L0 (-0.5, 20) -> (-39.5, 20)
  line L1 (-39.5, 20) -> (-40, 19.5)
  line L2 (-40, 19.5) -> (-40, 0.5)
  line L3 (-40, 0.5) -> (-39.5, 0)
  line L4 (-39.5, 0) -> (-0.5, 0)
  line L5 (-0.5, 0) -> (0, 0.5)
  line L6 (0, 0.5) -> (0, 19.5)
  line L7 (0, 19.5) -> (-0.5, 20)
  circle A0 centre (-20, 13) radius 5.25
extrude "Extrude3'" cut sketch "Sketch10" against normal blind 10 contours A0 bodies 7 in component "C section"
sketch "Sketch11" plane through (0, 0, 0) normal (0, 1, 0) x (1, 0, 0)
  line L0 (55, 0) -> (95, 0)
  line L1 (95, 0) -> (95, -20)
  line L2 (55, -20) -> (55, 0)
  line L3 (61, -20) -> (61, -21.5)
  line L4 (61, -21.5) -> (67, -21.5)
  line L5 (67, -21.5) -> (67, -20)
  line L6 (72, -20) -> (72, -21.5)
  line L7 (72, -21.5) -> (78, -21.5)
  line L8 (78, -21.5) -> (78, -20)
  line L9 (83, -20) -> (83, -21.5)
  line L10 (83, -21.5) -> (89, -21.5)
  line L11 (89, -21.5) -> (89, -20)
  line L12 (61, -20) -> (55, -20)
  line L13 (72, -20) -> (67, -20)
  line L14 (95, -20) -> (89, -20)
  line L15 (83, -20) -> (78, -20)
  line L16 (55, -10) -> (95, -10) construction
  line L17 (61, 0) -> (61, 1.5)
  line L18 (61, 1.5) -> (67, 1.5)
  line L19 (67, 1.5) -> (67, 0)
  line L20 (72, 0) -> (72, 1.5)
  line L21 (72, 1.5) -> (78, 1.5)
  line L22 (78, 1.5) -> (78, 0)
  line L23 (83, 0) -> (83, 1.5)
  line L24 (83, 1.5) -> (89, 1.5)
  line L25 (89, 1.5) -> (89, 0)
  line L26 (0, 0) -> (99, 0) construction
  dimension "d89" = 40
  dimension "d90" = 20
  dimension "d91" = 6
  dimension "d92" = 6
  dimension "d93" = 6
  dimension "d94" = 6
  dimension "d95" = 6
  dimension "d96" = 5
  constraint horizontal L0
  constraint vertical L1
  constraint horizontal L14
  constraint vertical L2
  constraint coincident L3.start L14
  constraint perpendicular L3 L14
  constraint perpendicular L3 L4
  constraint perpendicular L5 L14
  constraint coincident L6.start L14
  constraint perpendicular L6 L14
  constraint perpendicular L5 L7
  constraint perpendicular L8 L14
  constraint coincident L9.start L14
  constraint perpendicular L9 L14
  constraint perpendicular L9 L10
  constraint perpendicular L11 L14
  constraint collinear L12 L14
  constraint collinear L13 L14
  constraint collinear L14 L15
  constraint midpoint L2 L16.start
  constraint midpoint L1 L16.end
  constraint symmetric L3.start L16 L17.start
  constraint symmetric L3.end L16 L17.end
  constraint symmetric L4.end L16 L18.end
  constraint symmetric L5.end L16 L19.end
  constraint symmetric L6.start L16 L20.start
  constraint symmetric L6.end L16 L20.end
  constraint symmetric L7.end L16 L21.end
  constraint symmetric L8.end L16 L22.end
  constraint symmetric L9.start L16 L23.start
  constraint symmetric L9.end L16 L23.end
  constraint symmetric L10.end L16 L24.end
  constraint symmetric L11.end L16 L25.end
  constraint coincident L26.start origin
  constraint horizontal L26
  constraint coincident L0.start L26
  measures "d89" distance of L0.start L0.end
  measures "d90" distance of L0.start L2.start
  measures "d91" distance of L3.end L4.end
  measures "d92" distance of L6.end L7.end
  measures "d93" distance of L9.end L10.end
  measures "d94" distance of L2 L3
  measures "d95" distance of L1 L11
  measures "d96" distance of L5 L6
extrude "Extrude7" add sketch "Sketch11" along normal blind 1079 separate body makes body 14
fillet "Fillet4" radius 1 12 edges at (89, 539.5, 20) (89, 539.5, 21.5) (83, 539.5, 21.5) (83, 539.5, 20) (72, 539.5, 20) (72, 539.5, 21.5) (78, 539.5, 21.5) (78, 539.5, 20) (67, 539.5, 20) (67, 539.5, 21.5) (61, 539.5, 21.5) (61, 539.5, 20) on bodies 14
chamfer "Chamfer4" distance 0.5 angle 45 4 edges at (55, 539.5, 20) (95, 539.5, 20) (55, 539.5, 0) (95, 539.5, 0) on bodies 14
copy_body "Body->Comp6" bodies 14 removing the originals makes body 15 in component "Guide rail"
extrude "Extrude1'''" add 1 faces at (65.051, 0, 13.3723) along direction (0, -1, 0) blind 10 on bodies 15 bodies 15 in component "Guide rail"
delete_face "DeleteFace1" 1 faces at (55.3333, 353, 0.1667) on bodies 15 in component "Guide rail"
sketch "Sketch12" plane through (55, 0, 0) normal (-1, 0, 0) x (0, -1, 0)
  line L0 (10, 0) -> (10, 19.5)
  line L1 (10, 19.5) -> (-1079, 19.5)
  line L2 (-1079, 19.5) -> (-1079, 0)
  line L3 (10, 0) -> (0, 0)
  line L4 (0, 0) -> (0, 19.5)
  line L5 (0, 19.5) -> (10, 19.5)
  line L6 (10, 19.5) -> (10, 0)
  line L7 (-1079, 19.5) -> (-1069, 19.5)
  line L8 (-1069, 19.5) -> (-1069, 0)
  line L9 (-1069, 0) -> (-1079, 0)
  line L10 (-1079, 0) -> (-1079, 19.5)
  line L11 (-1079, 0) -> (10, 0)
  dimension "d104" = 10
  constraint horizontal L3
  constraint vertical L4
  constraint horizontal L5
  constraint vertical L6
  constraint coincident L1 L4.end
  constraint coincident L0.start L3.start
  constraint horizontal L7
  constraint vertical L8
  constraint horizontal L9
  constraint vertical L10
  constraint coincident L1.end L2.start
  constraint coincident L8.end L11
  measures "d104" distance of L1.end L7.end
extrude "Extrude2''" add sketch "Sketch12" along normal blind 25 contours L0 L1 L3 L4 L5 L6 L11 | L1 L2 L7 L8 L9 L10 L11 bodies 15 in component "Guide rail"
fillet "Fillet1'" radius 20 2 edges at (55, 0, 9.75) (55, 1069, 9.75) on bodies 15 in component "Guide rail"
delete_face "DeleteFace1'" 2 faces at (39.6667, 343.6667, 0.1667) (39.6667, -9.6667, 0.1667) on bodies 4 7 in component "C section"
delete_face "DeleteFace1''" 1 faces at (39.8333, 1040.6667, 0.3333) on bodies 9 in component "End closure 2"
fillet "Fillet2'" radius 1 12 edges at (89, 534.5, -1.5) (89, 534.5, 0) (67, 534.5, -1.5) (72, 534.5, 0) (72, 534.5, -1.5) (61, 534.5, -1.5) (61, 534.5, 0) (78, 534.5, -1.5) (83, 534.5, 0) (83, 534.5, -1.5) (78, 534.5, 0) (67, 534.5, 0) on bodies 15 in component "Guide rail"
sketch "Sketch13" plane through (0, -29, 0) normal (0, -1, 0) x (1, 0, 0)
  line L0 (0.5, 0) -> (40, 0)
  line L1 (40, 0) -> (40, 19.5)
  line L2 (40, 19.5) -> (39.5, 20)
  line L3 (39.5, 20) -> (0.5, 20)
  line L4 (0.5, 20) -> (0, 19.5)
  line L5 (0, 19.5) -> (0, 0.5)
  line L6 (0, 0.5) -> (0.5, 0)
  line L7 (0, 10) -> (18, 10) construction
  line L8 (8.8222, 59.9997) -> (-0.1896, 59.9997)
  line L9 (0.1659, -39.9997) -> (9.1778, -39.9997)
  line L10 (9.1778, -39.9997) -> (8.8222, 59.9997)
  line L11 (8.8222, 59.9997) -> (0, 10) construction
  line L12 (0, 10) -> (9.1778, -39.9997) construction
  line L13 (-0.1896, 59.9997) -> (0.1659, -39.9997)
  point P0 (0, 10)
  dimension "d139" = 100
  constraint perpendicular L5 L7
  constraint horizontal L8
  constraint parallel L8 L9
  constraint coincident L11 P0
  constraint coincident L12 P0
  constraint coincident P0 L7.start
  constraint parallel L10 L13
  constraint midpoint L7 L10
extrude "Extrude4'" add sketch "Sketch13" against normal up to surface (29 mm away) contours L0 L6 L9 L10 L13 | L3 L4 L5 L8 L10 L13 bodies 7 in component "C section"
sketch "Sketch14" plane through (0, 1060, 0) normal (0, 1, 0) x (-1, 0, 0)
  line L0 (-40, 19.5) -> (-40, 0)
  line L1 (-40, 0) -> (-0.5, 0)
  line L2 (-0.5, 0) -> (0, 0.5)
  line L3 (0, 0.5) -> (0, 19.5)
  line L4 (0, 19.5) -> (-0.5, 20)
  line L5 (-0.5, 20) -> (-39.5, 20)
  line L6 (-39.5, 20) -> (-40, 19.5)
  line L7 (-9.1778, -39.9997) -> (-8.8222, 59.9997)
  line L8 (-8.8222, 59.9997) -> (0.1896, 59.9997)
  line L9 (0.1896, 59.9997) -> (-0.1659, -39.9997)
  line L10 (-0.1659, -39.9997) -> (-9.1778, -39.9997)
  line L11 (0, 10) -> (-18, 10)
extrude "Extrude2'''" add sketch "Sketch14" against normal blind 29 contours L1 L2 L3 L7 L9 L11 | L1 L2 L7 L9 L10 | L3 L4 L5 L7 L8 L9 | L3 L4 L5 L7 L11 bodies 9 in component "End closure 2"
fillet "Fillet3'" radius 2 2 edges at (9.1778, -14.5, -39.9997) (8.8222, -14.5, 59.9997) on bodies 7 in component "C section"
fillet "Fillet1''" radius 2 2 edges at (8.8222, 1045.5, 59.9997) (9.1778, 1045.5, -39.9997) on bodies 9 in component "End closure 2"
extrude "Extrude5'" cut 1 faces at (18.3277, -10, 12.4842) along direction (0, -1, 0) blind 19 on bodies 7 bodies 7 in component "C section"
combine "Combine1" operation add target body 7 tool bodies 15 9 body 15 seen with x (1, 0, 0) y (0, 1, 0) z (0, 0, 1) at (10, -19, 0) in component "C section"
delete_face "DeleteFace2" 1 faces at (65.3333, 344, 19.8333) on bodies 7 in component "C section"
delete_face "DeleteFace3" 3 faces at (39.8333, 343.6667, 19.6667) (39.6667, -16, 19.8333) (39.6667, 1047, 19.8333) on bodies 4 7 in component "C section"
extrude "Extrude6'" add 1 faces at (51.8782, 1056.3966, 19.5) along direction (0, 0, 1) blind 0.5 on bodies 7 bodies 7 in component "C section"
extrude "Extrude7'" add 1 faces at (51.8782, -25.3966, 19.5) along direction (0, 0, 1) blind 0.5 on bodies 7 bodies 7 in component "C section"
delete_face "DeleteFace4" 2 faces at (46.9011, -18.9094, 6.6667) (46.9011, 1049.9094, 6.6667) on bodies 7 in component "C section"
extrude "Extrude8" add 1 faces at (56.6667, 1050, 6.6667) along direction (0, -1, 0) blind 19 on bodies 7 bodies 7 in component "C section"
extrude "Extrude9" add 1 faces at (56.6667, -19, 6.6667) along direction (0, 1, 0) blind 19 on bodies 7 bodies 7 in component "C section"
fillet "Fillet5" radius 60 4 edges at (8.9644, 1045.5, 20) (9.0356, 1045.5, 0) (9.0356, -14.5, 0) (8.9644, -14.5, 20) on bodies 7 in component "C section"
fillet "Fillet6" radius 25 2 edges at (65, 1031, 9.9999) (65, 0, 10) on bodies 7 in component "C section"
delete_face "DeleteFace5" 1 faces at (0, -19.3333, 2.5556) on bodies 7 in component "C section"
delete_face "DeleteFace6" 1 faces at (0, 1040.6667, 2.5556) on bodies 7 in component "C section"
delete_face "DeleteFace1'''" 1 faces at (23.8047, 99.8333, 16.1925) on bodies 5 in component "Rail"
extrude "Extrude1''''" cut 1 faces at (21.5166, 100, 13.2286) along direction (0, 1, 0) blind 50 on bodies 5 bodies 5 in component "Rail"
chamfer "Chamfer1'" distance 0.25 angle 45 1 edges at (15.2917, 150, 11.1738) on bodies 5 in component "Rail"
component "C section" placed x (1, 0, 0) y (0, 1, 0) z (0, 0, 1) at (0, 0, 0)
component "Rail" placed x (1, 0, 0) y (0, 1, 0) z (0, 0, 1) at (0, 466.25, 0)
component "Lead screw" placed x (1, 0, 0) y (0, 1, 0) z (0, 0, 1) at (20, -93, 13)
component "End closure 2" placed x (1, 0, 0) y (0, 1, 0) z (0, 0, 1) at (0, 0, 0)
component "Bearing 1" placed x (1, 0, 0) y (0, 1, 0) z (0, 0, 1) at (0, 0, 0)
component "Guide rail" placed x (1, 0, 0) y (0, 1, 0) z (0, 0, 1) at (10, -19, 0)
component "Bearing 2" placed x (1, 0, 0) y (0, 1, 0) z (0, 0, 1) at (0, 0, 0) in component "End closure 2"
equation "d11 = 1089 mm - 20 mm - 38 mm"
equation "d34 = -1089 mm - 30 mm"
equation "d38 = -10 mm - 19 mm"
named bodies: "C section", "Rail", "Lead screw", "End closure", "End closure 2"

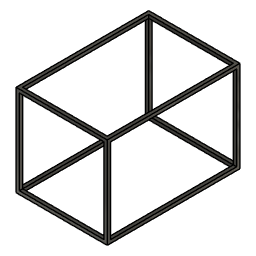
design "Welded Frame"
Autodesk Fusion 360 part; units mm, degrees
sketch "Sketch1" plane through (0, 0, 0) normal (1, 0, 0) x (0, 1, 0)
  line L0 (0, 0) -> (1600, 0)
  line L1 (1600, 0) -> (1600, 1100)
  line L2 (1600, 1100) -> (0, 1100)
  line L3 (0, 1100) -> (0, 0)
  line L4 (40, 40) -> (1560, 40)
  line L5 (1560, 40) -> (1560, 1060)
  line L6 (1560, 1060) -> (40, 1060)
  line L7 (40, 1060) -> (40, 40)
  dimension "d1" = 1600
  dimension "d2" = 1100
  dimension "d3" = -40
  constraint horizontal L0
  constraint vertical L1
  constraint horizontal L2
  constraint vertical L3
  constraint coincident L0.start L3.end
  measures "d1" distance of L0.start L0.end
  measures "d2" distance of L0.start L2.end
extrude "Extrude1" add sketch "Sketch1" against normal blind 1100 makes body 1
sketch "Sketch2" plane through (0, 0, 0) normal (0, -1, 0) x (1, 0, 0)
  line L0 (0, 0) -> (0, 1100)
  line L1 (0, 1100) -> (-1100, 1100)
  line L2 (-1100, 1100) -> (-1100, 0)
  line L3 (-1100, 0) -> (0, 0)
  line L4 (-1060, 40) -> (-40, 40)
  line L5 (-40, 40) -> (-40, 1060)
  line L6 (-40, 1060) -> (-1060, 1060)
  line L7 (-1060, 1060) -> (-1060, 40)
  dimension "d6" = -40
extrude "Extrude2" cut sketch "Sketch2" against normal blind 1600 contours L4 L5 L6 L7 bodies 1
sketch "Sketch3" plane through (0, 0, 1100) normal (0, 0, 1) x (-1, 0, 0)
  line L0 (0, 0) -> (0, -1600)
  line L1 (0, -1600) -> (1100, -1600)
  line L2 (1100, -1600) -> (1100, 0)
  line L3 (1100, 0) -> (0, 0)
  line L4 (40, -40) -> (40, -1560)
  line L5 (40, -1560) -> (1060, -1560)
  line L6 (1060, -1560) -> (1060, -40)
  line L7 (1060, -40) -> (40, -40)
  dimension "d9" = -40
extrude "Extrude3" cut sketch "Sketch3" against normal blind 1100 contours L4 L5 L6 L7 bodies 1
copy_body "Body->Comp1" bodies 1 removing the originals makes body 2 in component "Frame"
component "Frame" placed x (1, 0, 0) y (0, 1, 0) z (0, 0, 1) at (0, 0, 0)

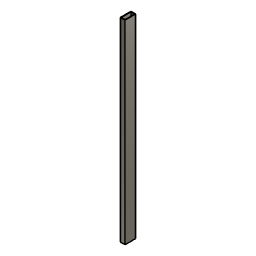
design "Nozzle holder"
Autodesk Fusion 360 part; units mm, degrees
sketch "Sketch1" plane through (0, 0, 0) normal (0, 0, 1) x (1, 0, 0)
  line L0 (0, 0) -> (29, 0)
  line L1 (29, 0) -> (29, 66.082)
  line L2 (29, 66.082) -> (0, 66.082)
  line L3 (0, 66.082) -> (0, 0)
  line L4 (3, 3) -> (26, 3)
  line L5 (26, 3) -> (26, 63.082)
  line L6 (26, 63.082) -> (3, 63.082)
  line L7 (3, 63.082) -> (3, 3)
  dimension "d1" = 29
  dimension "d2" = 66.082
  dimension "d3" = -3
  constraint horizontal L0
  constraint vertical L1
  constraint horizontal L2
  constraint vertical L3
  constraint coincident L0.start L3.end
  measures "d1" distance of L0.start L0.end
  measures "d2" distance of L0.start L2.end
extrude "Extrude1" add sketch "Sketch1" along normal blind 1200 makes body 1